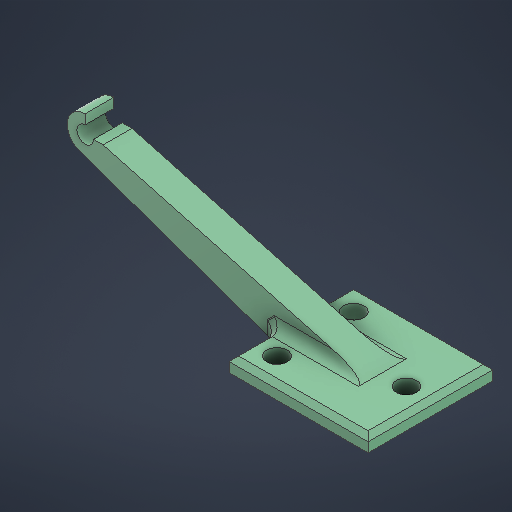
# Autodesk Inventor part: 1_1_5_attache_ressort
Saved by Autodesk Inventor 2026 (Build 300175000, 175)
## iProperties
Created: 2025-05-06
Part Number: 1_1_5_attache_ressort
Material: Generic
Document SubType Name: Modeling
Designer: remg9
Density: 1 g/cm^3
Appearance: Default
Author: remg9
Autodesk Inventor part; units mm, degrees
ref_plane "YZ Plane" through (0, 0, 0) normal (1, 0, 0) x (0, 1, 0)
ref_plane "XZ Plane" through (0, 0, 0) normal (0, 1, 0) x (-1, 0, 0)
ref_plane "XY Plane" through (0, 0, 0) normal (0, 0, 1) x (1, 0, 0)
sketch "Sketch1" plane through (0, 0, 0) normal (0, 1, 0) x (-1, 0, 0)
  line L0 (-14.5, 13) -> (14.5, 13)
  line L1 (14.5, 13) -> (14.5, -13)
  line L2 (14.5, -13) -> (-14.5, -13)
  line L3 (-14.5, -13) -> (-14.5, 13)
  line L4 (-14.5, 13) -> (14.5, -13) construction
  line L5 (14.5, 13) -> (-14.5, -13) construction
  point P0 (0, 0)
  dimension "d0" = 26
  dimension "d1" = 29
  constraints: 12 end point, 2 midpoint, 2 parallel, 1 horizontal, 1 perpendicular
  measures "d0" distance of L2.end L0.start
  measures "d1" distance of L1.end L2.end
extrude "Extrusion1" add sketch "Sketch1" along normal blind 3
sketch "Sketch2" plane through (0, 3, 0) normal (0, 1, 0) x (1, 0, 0)
  line L0 (14.5, 13) -> (-14.5, 13) projected
  line L1 (14.5, -13) -> (14.5, 13) projected
  line L2 (-14.5, -13) -> (14.5, -13) projected
  line L3 (-9.5, -8) -> (-9.5, 8) construction
  point P0 (0, 0)
  point P1 (9.5, 0)
  dimension "d4" = 13
  dimension "d5" = 5
  dimension "d6" = 5
  dimension "d7" = 5
  dimension "d8" = 19
  constraints: 2 end point, 1 vertical
  measures "d4" distance from line of L0 point (9.5, 0)
  measures "d5" distance from line of L1 point (9.5, 0)
  measures "d6" distance from line of L0 L3.end
  measures "d7" distance from line of L2 L3.start
  measures "d8" distance from line of point (9.5, 0) L3
hole "Hole1" at (-9.5, 3, -8) at (-9.5, 3, 8) at (9.5, 3, 0) direction (0, -1, 0) diameter 4.3 end through all
sketch "Sketch8" plane through (0, 0, 0) normal (0, 0, 1) x (1, 0, 0)
  line L0 (14.5, 3) -> (-14.5, 3) projected
  line L1 (14.5, 0) -> (-14.5, 0) projected
  line L2 (-14.5, 0) -> (-55.7409, 14.4613)
  circle A0 centre (-54.5, 18) radius 3.75 construction
  circle A1 centre (-54.5, 18) radius 1.75 construction
  line L3 (-14.5, 0) -> (-14.5, 3) projected
  line L4 (-50.75, 18) -> (-52.75, 18)
  line L5 (-54.5, 19.75) -> (-54.5, 21.75)
  arc A2 (-54.5, 21.75) -> (-55.7409, 14.4613) centre (-54.5, 18) ccw
  arc A3 (-54.5, 19.75) -> (-52.75, 18) centre (-54.5, 18) ccw
  line L6 (14.5, 0) -> (14.5, 3) projected
  line L7 (-50.75, 18) -> (4.5, 3)
  line L8 (-14.5, 3) -> (14.5, 3) projected
  point P0 (0, 0)
  point P1 (4.5, 3)
  dimension "d64" = 7.5
  dimension "d65" = 3.5
  dimension "d66" = 40
  dimension "d67" = 15
  dimension "d68" = 2
  dimension "d70" = 10
  constraints: 10 point on circle, 8 end point, 4 centre point, 3 tangent, 2 concentric, 1 coincident, 1 horizontal, 1 point on line, 1 vertical
  measures "d64" diameter of A0
  measures "d65" diameter of A1
  measures "d66" distance from line of L3 A0.centre
  measures "d67" distance from line of L0 A0.centre
  measures "d68" distance of L4.start L4.end
  measures "d70" distance from line of L6 L7.end
extrude "Extrusion4" add sketch "Sketch8" along normal mid plane 6 contours L0 L3 L2 A2 L5 A3 L4 L7
fillet "Fillet3" radius 2 4 edges at (-5, 3, -3) (-5, 3, 3) (-14.5, 1.5, -3) (-14.5, 1.5, 3)
chamfer "Chamfer4" distance 1 angle 45 7 edges at (0, 3, -13) (14.5, 3, 0) (-14.5, 3, 9) (-15.0858, 3.5858, 3.5858) (0, 3, 13) (-14.5, 3, -9) (-15.0858, 3.5858, -3.5858)
body "Solid1"
